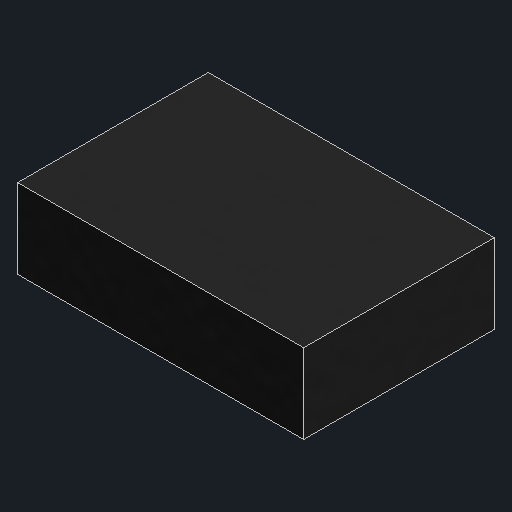
# Autodesk Inventor part: usb_microB_plug_90deg
Saved by Autodesk Inventor 2027.1 (Build 311270010, 270A)
## iProperties
Created: 2026-10-29
Part Number: usb_microB_plug_90deg
Material: Generic
Document SubType Name: Modeling
Designer: alexg
Density: 1 g/cm^3
Appearance: Black
Author: alexg
Autodesk Inventor part; units mm, degrees
ref_plane "YZ Plane" through (0, 0, 0) normal (1, 0, 0) x (0, 1, 0)
ref_plane "XZ Plane" through (0, 0, 0) normal (0, 1, 0) x (-1, 0, 0)
ref_plane "Work Plane1" through (0, 0, -4.1) normal (0, 0, 1) x (1, 0, 0)
sketch "Body sketch" plane through (0, 0, -4.1) normal (0, 0, 1) x (1, 0, 0)
  line L0 (-12.93, -28.34) -> (5.07, -28.34)
  line L1 (5.07, -28.34) -> (5.07, -23.34)
  line L2 (5.07, -23.34) -> (-12.93, -23.34)
  line L3 (-12.93, -23.34) -> (-12.93, -28.34)
  constraints: 8 end point, 2 parallel, 1 horizontal, 1 perpendicular
extrude "Body" add sketch "Body sketch" against normal blind 12
body "Solid1"
